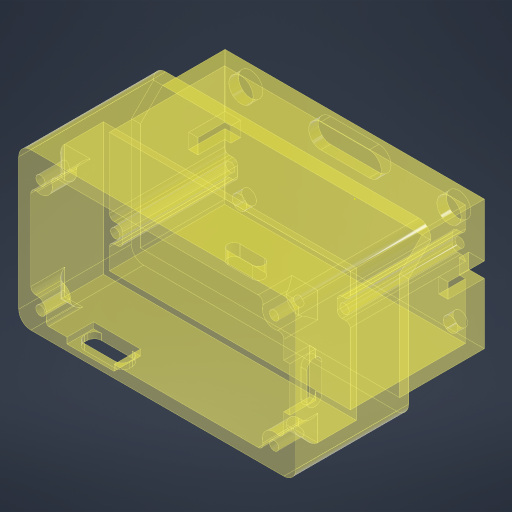
# Autodesk Inventor part: INNER
Saved by Autodesk Inventor 2024.3 (Build 283343000, 343)
## iProperties
Created: 2026-06-30
Part Number: INNER
Material: Generic
Document SubType Name: Modeling
Designer: REMOTE
Density: 1 g/cm^3
Appearance: Clear - Yellow
Author: REMOTE
Autodesk Inventor part; units mm, degrees
sketch "Sketch1" plane through (0, 0, 0) normal (0, 0, 1) x (1, 0, 0)
  line L0 (-26.8, -13.4) -> (26.8, -13.4)
  line L1 (26.8, -13.4) -> (26.8, 13.4)
  line L2 (26.8, 13.4) -> (-26.8, 13.4)
  line L3 (-26.8, 13.4) -> (-26.8, -13.4)
  line L4 (-26.8, -13.4) -> (26.8, 13.4) construction
  line L5 (26.8, -13.4) -> (-26.8, 13.4) construction
  point P0 (0, 0)
  dimension "d0" = 53.6
  dimension "d1" = 26.8
  constraints: 12 end point, 2 midpoint, 2 parallel, 1 horizontal, 1 perpendicular
  measures "d0" distance of L2.end L1.end
  measures "d1" distance of L1.end L0.end
extrude "Extrusion1" add sketch "Sketch1" along normal blind 2
sketch "Sketch2" plane through (0, 0, 2) normal (0, 0, 1) x (1, 0, 0)
  line L0 (26.8, -13.4) -> (26.8, 13.4) projected
  line L1 (26.8, 13.4) -> (-26.8, 13.4) projected
  line L2 (-26.8, 13.4) -> (-26.8, -13.4) projected
  line L3 (-26.8, -13.4) -> (26.8, -13.4) projected
  line L4 (-25.8, 12.4) -> (25.8, 12.4)
  line L5 (25.8, 12.4) -> (25.8, -12.4)
  line L6 (25.8, -12.4) -> (-25.8, -12.4)
  line L7 (-25.8, -12.4) -> (-25.8, 12.4)
  point P0 (0, 0)
  dimension "d4" = 1
  constraints: 8 end point, 3 other
  measures "d4" distance between parallel lines of L1 L4
extrude "Extrusion2" add sketch "Sketch2" along normal blind 15.5
sketch "Sketch3" plane through (0, 0, 2) normal (0, 0, 1) x (1, 0, 0)
  circle A0 centre (21.825, -10.5) radius 1.5 projected
  circle A1 centre (-21.825, -10.5) radius 1.5 projected
  point P0 (0, 0)
ref_plane "Work Plane1" through (-35.75, -21, -2) normal (0, 0, -1) x (0, 1, 0)
extrude "Extrusion3" cut sketch "Sketch3" against normal up to surface (4 mm away)
sketch "Sketch4" plane through (26.8, -13.4, 0) normal (1, 0, 0) x (0, 0, -1)
  line L0 (-7.2, 15.4) -> (0, 15.4) projected
  line L1 (-7.2, 12.9) -> (-7.2, 15.4) projected
  line L2 (0, 12.9) -> (-7.2, 12.9) projected
  line L3 (0, 26.8) -> (0, 0) projected
  line L4 (0, 15.7) -> (-7.5, 15.7)
  line L5 (-7.5, 15.7) -> (-7.5, 12.6)
  line L6 (-7.5, 12.6) -> (0, 12.6)
  point P0 (0, 13.4)
  point P1 (0, 12.6)
  dimension "d9" = 0.3
  constraints: 6 end point, 2 other
  measures "d9" distance between parallel lines of L0 L4
ref_plane "Work Plane2" through (-35.75, -21, -2) normal (-1, 0, 0) x (0, 0, 1)
extrude "Extrusion4" cut sketch "Sketch4" against normal up to surface (62.55 mm away)
sketch "Sketch5" plane through (0, 0, 0) normal (0, 0, -1) x (-1, 0, 0)
  point P0 (0, 0)
sketch "Sketch6" plane through (0, 0, 0) normal (0, 0, -1) x (-1, 0, 0)
  line L0 (26.8, -0.8) -> (-26.8, -0.8) projected
  line L1 (-26.8, 2.3) -> (26.8, 2.3) projected
  line L2 (25.8, -0.8) -> (25.8, 2.3) projected
  line L3 (-25.8, 2.3) -> (-25.8, -0.8) projected
  point P0 (0, 0)
extrude "Extrusion5" add sketch "Sketch6" against normal up to surface (2 mm away)
ref_plane "Work Plane3" through (-35.75, -21, -2) normal (0, 0, -1) x (0, 1, 0)
sketch "Sketch7" plane through (0, 0, 2) normal (0, 0, 1) x (1, 0, 0)
  line L0 (-23.9, 2) -> (-26.9, 2)
  line L1 (-26.9, -0.5) -> (-23.9, -0.5)
  line L2 (-23.9, -0.5) -> (-23.9, 2)
  line L3 (26.9, 2) -> (23.9, 2)
  line L4 (23.9, 2) -> (23.9, -0.5)
  line L5 (23.9, -0.5) -> (26.9, -0.5)
  line L6 (-26.9, 2.3) -> (-23.6, 2.3)
  line L7 (-23.6, 2.3) -> (-23.6, -0.8)
  line L8 (-23.6, -0.8) -> (-26.9, -0.8)
  line L9 (26.9, 2.3) -> (23.6, 2.3)
  line L10 (23.6, 2.3) -> (23.6, -0.8)
  line L11 (23.6, -0.8) -> (26.9, -0.8)
  line L12 (-25.8, -0.8) -> (-25.8, -12.4)
  line L13 (-25.8, -12.4) -> (25.8, -12.4)
  line L14 (25.8, -12.4) -> (25.8, -0.8)
  line L15 (25.8, 2.3) -> (25.8, -0.8)
  line L16 (25.8, 2.3) -> (25.8, 12.4)
  line L17 (25.8, 12.4) -> (-25.8, 12.4)
  line L18 (-25.8, 12.4) -> (-25.8, 2.3)
  line L19 (-25.8, -0.8) -> (-25.8, 2.3)
  circle A0 centre (-21.825, -10.5) radius 1.5
  circle A1 centre (21.825, -10.5) radius 1.5
  point P0 (0, 0)
  point P1 (25.8, -0.8)
  point P2 (-25.8, 2.3)
extrude "Extrusion6" cut sketch "Sketch7" against normal up to surface (4 mm away) contours L2 L1 L19 L0 | L0 L19 L6 L7 L8 L1 L2 | L15 L3 L4 L5 L11 L10 L9 | L15 L5 L4 L3
sketch "Sketch8" plane through (0, 0, 2) normal (0, 0, 1) x (1, 0, 0)
  circle A0 centre (21.825, -10.5) radius 1.5 projected
  circle A1 centre (-21.825, -10.5) radius 1.5 projected
  line L0 (25.8, -0.8) -> (23.6, -0.8) projected
  line L1 (23.6, -0.8) -> (23.6, 2.3) projected
  line L2 (23.6, 2.3) -> (25.8, 2.3) projected
  line L3 (25.8, 2.3) -> (25.8, 12.4) projected
  line L4 (25.8, 12.4) -> (-25.8, 12.4) projected
  line L5 (-25.8, 12.4) -> (-25.8, 2.3) projected
  line L6 (-25.8, 2.3) -> (-23.6, 2.3) projected
  line L7 (-23.6, 2.3) -> (-23.6, -0.8) projected
  line L8 (-23.6, -0.8) -> (-25.8, -0.8) projected
  line L9 (-25.8, -0.8) -> (-25.8, -12.4) projected
  line L10 (-25.8, -12.4) -> (25.8, -12.4) projected
  line L11 (25.8, -12.4) -> (25.8, -0.8) projected
  circle A2 centre (21.5, 9.8) radius 2.5
  circle A3 centre (-21.5, 9.8) radius 2.5
  point P0 (0, 0)
  dimension "d18" = 5
  dimension "d19" = 5
  dimension "d20" = 43
  dimension "d21" = 4.3
  dimension "d22" = 2.6
  dimension "d23" = 2.6
  constraints: 2 centre point
  measures "d18" diameter of A2
  measures "d19" diameter of A3
  measures "d20" distance of A2.centre A3.centre
  measures "d21" distance from line of L3 A2.centre
  measures "d22" distance from line of L4 A2.centre
  measures "d23" distance from line of L4 A3.centre
ref_plane "Work Plane4" through (-35.75, -21, -2) normal (0, 0, -1) x (0, 1, 0)
extrude "Extrusion7" cut sketch "Sketch8" against normal up to surface (4 mm away) contours A2 | A3
sketch "Sketch9" plane through (0, 0, 17.5) normal (0, 0, 1) x (1, 0, 0)
  line L0 (26.8, 13.4) -> (-26.8, 13.4) projected
  line L1 (-26.8, 13.4) -> (-26.8, -13.4) projected
  line L2 (-26.8, -13.4) -> (26.8, -13.4) projected
  line L3 (26.8, -13.4) -> (26.8, 13.4) projected
  line L4 (-25.8, 12.4) -> (25.8, 12.4) projected
  line L5 (25.8, 12.4) -> (25.8, -12.4) projected
  line L6 (25.8, -12.4) -> (-25.8, -12.4) projected
  line L7 (-25.8, -12.4) -> (-25.8, 12.4) projected
  line L8 (26.9, -13.5) -> (-26.9, -13.5) projected
  line L9 (-26.9, -13.5) -> (-26.9, 13.5) projected
  line L10 (-26.9, 13.5) -> (26.9, 13.5) projected
  line L11 (26.9, 13.5) -> (26.9, -13.5) projected
  line L12 (-28.75, 16.25) -> (28.75, 16.25) projected
  line L13 (-28.75, -16.25) -> (-28.75, 16.25) projected
  line L14 (28.75, -16.25) -> (-28.75, -16.25) projected
  line L15 (28.75, 16.25) -> (28.75, -16.25) projected
  line L16 (28.65, -16.15) -> (-28.65, -16.15)
  line L17 (-28.65, -16.15) -> (-28.65, 16.15)
  line L18 (-28.65, 16.15) -> (28.65, 16.15)
  line L19 (28.65, 16.15) -> (28.65, -16.15)
  point P0 (0, 0)
  dimension "d26" = 0.1
  constraints: 8 end point, 3 other
  measures "d26" distance between parallel lines of L15 L19
extrude "Extrusion8" add sketch "Sketch9" along normal blind 2.3 contours L3 L2 L1 L0 | L8 L9 L10 L11 | L16 L17 L18 L19
sketch "Sketch10" plane through (0, 0, 19.8) normal (0, 0, 1) x (1, 0, 0)
  line L0 (28.65, 16.15) -> (-28.65, 16.15) projected
  line L1 (-28.65, 16.15) -> (-28.65, -16.15) projected
  line L2 (-28.65, -16.15) -> (28.65, -16.15) projected
  line L3 (28.65, -16.15) -> (28.65, 16.15) projected
  line L4 (-25.8, 12.4) -> (25.8, 12.4) projected
  line L5 (25.8, 12.4) -> (25.8, -12.4) projected
  line L6 (25.8, -12.4) -> (-25.8, -12.4) projected
  line L7 (-25.8, -12.4) -> (-25.8, 12.4) projected
  line L8 (26.15, -13.65) -> (-26.15, -13.65)
  line L9 (-26.15, -13.65) -> (-26.15, 13.65)
  line L10 (-26.15, 13.65) -> (26.15, 13.65)
  line L11 (26.15, 13.65) -> (26.15, -13.65)
  point P0 (0, 0)
  dimension "d29" = 2.5
  constraints: 8 end point, 3 other
  measures "d29" distance between parallel lines of L2 L8
extrude "Extrusion9" add sketch "Sketch10" along normal blind 21 contours L3 L2 L1 L0
sketch "Sketch11" plane through (0, 0, 19.8) normal (0, 0, 1) x (1, 0, 0)
  line L0 (26.15, -13.65) -> (26.15, 13.65) projected
  line L1 (26.15, 13.65) -> (-26.15, 13.65) projected
  line L2 (-26.15, 13.65) -> (-26.15, -13.65) projected
  line L3 (-26.15, -13.65) -> (26.15, -13.65) projected
  line L4 (-25.8, 12.4) -> (25.8, 12.4) projected
  line L5 (25.8, 12.4) -> (25.8, -12.4) projected
  line L6 (25.8, -12.4) -> (-25.8, -12.4) projected
  line L7 (-25.8, -12.4) -> (-25.8, 12.4) projected
  point P0 (0, 0)
extrude "Extrusion10" add sketch "Sketch11" along normal blind 6
sketch "Sketch13" plane through (0, 0, 25.8) normal (0, 0, 1) x (1, 0, 0)
  line L0 (-26.15, 13.65) -> (26.15, 13.65) projected
  line L1 (-26.15, -13.65) -> (-26.15, 13.65) projected
  line L2 (26.15, -13.65) -> (-26.15, -13.65) projected
  line L3 (26.15, 13.65) -> (26.15, -13.65) projected
  line L4 (-25.8, 12.4) -> (25.8, 12.4) projected
  line L5 (25.8, 12.4) -> (25.8, -12.4) projected
  line L6 (25.8, -12.4) -> (-25.8, -12.4) projected
  line L7 (-25.8, -12.4) -> (-25.8, 12.4) projected
  line L8 (25.8, -12.4) -> (26.15, -12.4)
  line L9 (25.8, 12.4) -> (26.15, 12.4)
  line L10 (-25.8, -12.4) -> (-26.15, -12.4)
  line L11 (-25.8, 12.4) -> (-26.15, 12.4)
  point P0 (0, 0)
  constraints: 8 end point, 4 perpendicular, 4 point on line
extrude "Extrusion11" cut sketch "Sketch13" against normal up to surface (23.8 mm away) contours L11 L7 L10 L1 | L3 L8 L5 L9
sketch "Sketch15" plane through (0, 0, 2) normal (0, 0, 1) x (1, 0, 0)
  circle A0 centre (-21.5, 9.8) radius 2.5 projected
  circle A1 centre (21.5, 9.8) radius 2.5 projected
  circle A2 centre (21.825, -10.5) radius 1.5 projected
  circle A3 centre (-21.825, -10.5) radius 1.5 projected
  line L0 (23.6, -0.8) -> (26.15, -0.8) projected
  line L1 (23.6, -0.8) -> (23.6, 2.3) projected
  line L2 (26.15, 2.3) -> (23.6, 2.3) projected
  line L3 (26.15, 12.4) -> (26.15, 2.3) projected
  line L4 (-26.15, 12.4) -> (26.15, 12.4) projected
  line L5 (-26.15, 2.3) -> (-26.15, 12.4) projected
  line L6 (-26.15, 2.3) -> (-23.6, 2.3) projected
  line L7 (-23.6, 2.3) -> (-23.6, -0.8) projected
  line L8 (-26.15, -0.8) -> (-23.6, -0.8) projected
  line L9 (-26.15, -12.4) -> (-26.15, -0.8) projected
  line L10 (-26.15, -12.4) -> (26.15, -12.4) projected
  line L11 (26.15, -0.8) -> (26.15, -12.4) projected
  line L12 (26.15, -12.4) -> (24.9, -12.4)
  line L13 (24.9, -12.4) -> (24.9, 12.4)
  line L14 (24.9, 12.4) -> (26.15, 12.4)
  line L15 (26.15, 12.4) -> (26.15, -12.4)
  line L16 (-26.15, -12.4) -> (-24.9, -12.4)
  line L17 (-24.9, -12.4) -> (-24.9, 12.4)
  line L18 (-24.9, 12.4) -> (-26.15, 12.4)
  line L19 (-26.15, 12.4) -> (-26.15, -12.4)
  point P0 (0, 0)
  point P1 (-24.9, 2.3)
  point P2 (-24.9, -0.8)
  point P3 (24.9, 2.3)
  point P4 (24.9, -0.8)
  dimension "d36" = 1.25
  dimension "d37" = 1.25
  constraints: 16 end point, 4 parallel, 2 horizontal, 2 perpendicular, 2 point on line
  measures "d36" distance of L13.end L14.end
  measures "d37" distance of L18.end L17.end
extrude "Extrusion12" add sketch "Sketch15" along normal up to surface (23.8 mm away) contours L0 L11 L10 L13 | L13 L4 L3 L2 | L10 L9 L8 L17 | L17 L6 L5 L4
sketch "Sketch16" plane through (0, 0, 2) normal (0, 0, 1) x (1, 0, 0)
  circle A0 centre (-21.825, -10.5) radius 1.5 projected
  circle A1 centre (21.825, -10.5) radius 1.5 projected
  circle A2 centre (21.5, 9.8) radius 2.5 projected
  circle A3 centre (-21.5, 9.8) radius 2.5 projected
  line L0 (-24.9, -0.8) -> (-24.9, -12.4) projected
  line L1 (-24.9, -12.4) -> (24.9, -12.4) projected
  line L2 (24.9, -12.4) -> (24.9, -0.8) projected
  line L3 (23.6, -0.8) -> (24.9, -0.8) projected
  line L4 (23.6, -0.8) -> (23.6, 2.3) projected
  line L5 (24.9, 2.3) -> (23.6, 2.3) projected
  line L6 (24.9, 2.3) -> (24.9, 12.4) projected
  line L7 (-24.9, 12.4) -> (24.9, 12.4) projected
  line L8 (-24.9, 12.4) -> (-24.9, 2.3) projected
  line L9 (-24.9, 2.3) -> (-23.6, 2.3) projected
  line L10 (-23.6, 2.3) -> (-23.6, -0.8) projected
  line L11 (-24.9, -0.8) -> (-23.6, -0.8) projected
  circle A4 centre (23.7, 5.1) radius 0.95
  circle A5 centre (-23.7, -5.1) radius 0.95
  line L12 (22.2, 7.1) -> (25.2, 7.1)
  line L13 (25.2, 7.1) -> (25.2, 3.1)
  line L14 (25.2, 3.1) -> (22.2, 3.1)
  line L15 (22.2, 3.1) -> (22.2, 7.1)
  line L16 (22.2, 7.1) -> (25.2, 3.1) construction
  line L17 (25.2, 7.1) -> (22.2, 3.1) construction
  line L18 (-22.2, -3.1) -> (-25.2, -3.1)
  line L19 (-25.2, -3.1) -> (-25.2, -7.1)
  line L20 (-25.2, -7.1) -> (-22.2, -7.1)
  line L21 (-22.2, -7.1) -> (-22.2, -3.1)
  line L22 (-22.2, -3.1) -> (-25.2, -7.1) construction
  line L23 (-25.2, -3.1) -> (-22.2, -7.1) construction
  point P0 (0, 0)
  point P1 (-24.9, -3.1)
  point P2 (-24.9, -7.1)
  point P3 (24.9, 3.1)
  point P4 (24.9, 7.1)
  dimension "d40" = 1.9
  dimension "d41" = 1.2
  dimension "d42" = 7.3
  dimension "d43" = 1.9
  dimension "d44" = 1.2
  dimension "d45" = 7.3
  dimension "d46" = 3
  dimension "d47" = 4
  dimension "d48" = 3
  dimension "d49" = 4
  constraints: 24 end point, 4 midpoint, 4 parallel, 2 centre point, 2 horizontal, 2 perpendicular
  measures "d40" diameter of A4
  measures "d41" distance from line of L6 A4.centre
  measures "d42" distance from line of L7 A4.centre
  measures "d43" diameter of A5
  measures "d44" distance from line of L0 A5.centre
  measures "d45" distance from line of L1 A5.centre
  measures "d46" distance of L13.end L14.end
  measures "d47" distance of L12.end L13.end
  measures "d48" distance of L20.end L19.end
  measures "d49" distance of L19.end L18.end
extrude "Extrusion13" add sketch "Sketch16" along normal up to surface (23.8 mm away) contours L18 L21 L20 L0 | L6 L14 L15 L12
fillet "Fillet1" radius 1 8 edges at (22.2, 7.1, 13.9) (24.9, 7.1, 13.9) (22.2, 3.1, 13.9) (24.9, 3.1, 13.9) (-24.9, -3.1, 13.9) (-22.2, -3.1, 13.9) (-22.2, -7.1, 13.9) (-24.9, -7.1, 13.9)
sketch "Sketch17" plane through (0, 0, 40.8) normal (0, 0, 1) x (1, 0, 0)
  line L0 (-28.65, 16.15) -> (-28.65, -16.15) projected
  line L1 (-28.65, -16.15) -> (28.65, -16.15) projected
  line L2 (28.65, -16.15) -> (28.65, 16.15) projected
  line L3 (28.65, 16.15) -> (-28.65, 16.15) projected
  line L4 (26.15, -13.65) -> (-26.15, -13.65) projected
  line L5 (-26.15, -13.65) -> (-26.15, 13.65) projected
  line L6 (-26.15, 13.65) -> (26.15, 13.65) projected
  line L7 (26.15, 13.65) -> (26.15, -13.65) projected
  line L8 (26.15, -13.65) -> (24.15, -13.65)
  line L9 (26.15, -13.65) -> (-26.15, -13.65) projected
  line L10 (24.15, -13.65) -> (24.15, -11.65)
  circle A0 centre (24.15, -11.65) radius 0.95
  circle A1 centre (24.15, -11.65) radius 2.45
  point P0 (0, 0)
  point P1 (26.15, -10.2349)
  point P2 (22.7349, -13.65)
  dimension "d104" = 2
  dimension "d105" = 2
  dimension "d106" = 1.9
  dimension "d107" = 1.5
  constraints: 4 end point, 2 centre point, 1 coincident, 1 perpendicular, 1 point on line
  measures "d104" distance of L4.start L8.end
  measures "d105" distance of L8.end L10.end
  measures "d106" diameter of A0
  measures "d107" radial gap between concentric circles of A0 A1
fillet "Fillet3" radius 2.5 4 edges at (-28.65, -16.15, 29.15) (28.65, -16.15, 29.15) (28.65, 16.15, 29.15) (-28.65, 16.15, 29.15)
sketch "Sketch20" plane through (0, 0, 40.8) normal (0, 0, 1) x (1, 0, 0)
  line L0 (-18.27, -14.5) -> (-18.27, -12.6) projected
  line L1 (-9.33, -12.6) -> (-9.33, -14.5) projected
  line L2 (27, 4.21) -> (20.1, 4.21)
  line L3 (27, 4.21) -> (27, 2.89) projected
  line L4 (27, -2.89) -> (27, 2.89) projected
  line L5 (27, -2.89) -> (27, -4.21) projected
  line L6 (27, -4.21) -> (20.1, -4.21)
  line L7 (-16.9746, -14.5) -> (-18.27, -14.5) projected
  line L8 (-16.9746, -14.5) -> (-13.3125, -14.5) projected
  line L9 (-13.2625, -14.5) -> (-10.6254, -14.5) projected
  line L10 (-16.9746, -14.5) -> (-10.6254, -14.5) projected
  line L11 (-9.33, -14.5) -> (-10.6254, -14.5) projected
  line L12 (-8.93, -12.6) -> (-8.93, -14.9)
  line L13 (-8.93, -14.9) -> (-10.6254, -14.9)
  line L14 (-13.2625, -14.9) -> (-10.6254, -14.9)
  line L15 (-16.9746, -14.9) -> (-10.6254, -14.9)
  line L16 (-16.9746, -14.9) -> (-18.67, -14.9)
  line L17 (-18.67, -14.9) -> (-18.67, -12.6)
  line L18 (20.1, 4.61) -> (27.4, 4.61)
  line L19 (27.4, 4.61) -> (27.4, 2.89)
  line L20 (27.4, 2.89) -> (27.4, -2.89)
  line L21 (27.4, -2.89) -> (27.4, -4.61)
  line L22 (27.4, -4.61) -> (20.1, -4.61)
  arc A0 (28.65, 13.65) -> (26.15, 16.15) centre (26.15, 13.65) ccw projected
  line L23 (28.65, -13.65) -> (28.65, 13.65) projected
  arc A1 (26.15, -16.15) -> (28.65, -13.65) centre (26.15, -13.65) ccw projected
  line L24 (-26.15, -16.15) -> (26.15, -16.15) projected
  arc A2 (-28.65, -13.65) -> (-26.15, -16.15) centre (-26.15, -13.65) ccw projected
  line L25 (-28.65, 13.65) -> (-28.65, -13.65) projected
  arc A3 (-26.15, 16.15) -> (-28.65, 13.65) centre (-26.15, 13.65) ccw projected
  line L26 (26.15, 16.15) -> (-26.15, 16.15) projected
  line L27 (-23, -6.2221) -> (-23, 2.7221) projected
  line L28 (-21.5042, 10.2) -> (-5.8, 10.2) projected
  arc A4 (-4.6002, 9.0243) -> (-5.8, 10.2) centre (-5.8, 9) ccw projected
  arc A5 (-4.6002, 9.0243) -> (-4.6, 7.7755) centre (-4.1, 8.4) ccw projected
  line L29 (-4.6, -2.3745) -> (-4.6, -9.9) projected
  line L30 (-4.6, -9.9) -> (22.0278, -9.9) projected
  line L31 (22.0278, -8.9) -> (-2.5, -8.9) projected
  line L32 (-2.5, -8.9) -> (-2.5, -6.4889) projected
  arc A6 (-2.5, -6.4889) -> (-0.5, -4.7) centre (-2.3, -4.7) ccw projected
  line L33 (-0.5, -4.7) -> (-0.5, 4.7) projected
  arc A7 (-0.5, 4.7) -> (-2.5, 6.4889) centre (-2.3, 4.7) ccw projected
  line L34 (-2.5, 6.4889) -> (-2.5, 8.9) projected
  line L35 (-2.5, 8.9) -> (22.0278, 8.9) projected
  line L36 (22.0278, 9.9) -> (-3.4676, 9.9) projected
  arc A8 (-3.4676, 9.9) -> (-5.8, 11.5) centre (-5.8, 9) ccw projected
  line L37 (-5.8, 11.5) -> (-21.5042, 11.5) projected
  arc A9 (28.65, 13.65) -> (26.15, 16.15) centre (26.15, 13.65) ccw projected
  line L38 (28.65, -13.65) -> (28.65, 13.65) projected
  arc A10 (26.15, -16.15) -> (28.65, -13.65) centre (26.15, -13.65) ccw projected
  line L39 (-26.15, -16.15) -> (26.15, -16.15) projected
  arc A11 (-28.65, -13.65) -> (-26.15, -16.15) centre (-26.15, -13.65) ccw projected
  line L40 (-28.65, 13.65) -> (-28.65, -13.65) projected
  arc A12 (-26.15, 16.15) -> (-28.65, 13.65) centre (-26.15, 13.65) ccw projected
  line L41 (26.15, 16.15) -> (-26.15, 16.15) projected
  line L42 (-23, -6.2221) -> (-23, 2.7221) projected
  line L43 (-21.5042, 10.2) -> (-5.8, 10.2) projected
  arc A13 (-4.6002, 9.0243) -> (-5.8, 10.2) centre (-5.8, 9) ccw projected
  arc A14 (-4.6002, 9.0243) -> (-4.6, 7.7755) centre (-4.1, 8.4) ccw projected
  line L44 (-4.6, -2.3745) -> (-4.6, -9.9) projected
  line L45 (-4.6, -9.9) -> (22.0278, -9.9) projected
  line L46 (22.0278, -8.9) -> (-2.5, -8.9) projected
  line L47 (-2.5, -8.9) -> (-2.5, -6.4889) projected
  arc A15 (-2.5, -6.4889) -> (-0.5, -4.7) centre (-2.3, -4.7) ccw projected
  line L48 (-0.5, -4.7) -> (-0.5, 4.7) projected
  arc A16 (-0.5, 4.7) -> (-2.5, 6.4889) centre (-2.3, 4.7) ccw projected
  line L49 (-2.5, 6.4889) -> (-2.5, 8.9) projected
  line L50 (-2.5, 8.9) -> (22.0278, 8.9) projected
  line L51 (22.0278, 9.9) -> (-3.4676, 9.9) projected
  arc A17 (-3.4676, 9.9) -> (-5.8, 11.5) centre (-5.8, 9) ccw projected
  line L52 (-5.8, 11.5) -> (-21.5042, 11.5) projected
  line L53 (26.15, -13.65) -> (-26.15, -13.65) projected
  line L54 (26.15, 13.65) -> (26.15, -13.65) projected
  line L55 (13.1442, 5) -> (13.1442, -5) projected
  line L56 (13.1442, -5) -> (24.1442, -5) projected
  line L57 (24.1442, -5) -> (24.1442, 5) projected
  line L58 (24.1442, 5) -> (13.1442, 5) projected
  line L59 (13.1442, 5) -> (13.1442, -5) projected
  line L60 (13.1442, -5) -> (24.1442, -5) projected
  line L61 (24.1442, -5) -> (24.1442, 5) projected
  line L62 (24.1442, 5) -> (13.1442, 5) projected
  circle A18 centre (24.15, 11.65) radius 1.05 projected
  circle A19 centre (-24.15, -11.65) radius 1.05 projected
  circle A20 centre (24.15, -11.65) radius 1.05 projected
  circle A21 centre (24.15, 11.65) radius 1.05 projected
  circle A22 centre (-24.15, -11.65) radius 1.05 projected
  circle A23 centre (24.15, -11.65) radius 1.05 projected
  circle A24 centre (-24.15, 11.65) radius 1.05 projected
  circle A25 centre (-24.15, 11.65) radius 1.05 projected
  line L63 (22.0278, -9.9) -> (22.0278, -8.9) projected
  line L64 (22.0278, 8.9) -> (22.0278, 9.9) projected
  line L65 (-21.5042, 11.5) -> (-21.5042, 10.2) projected
  line L66 (-25.3, -8.7322) -> (-23, -8.7322) projected
  circle A26 centre (-24.15, 11.65) radius 1.05 projected
  circle A27 centre (-24.15, 11.65) radius 1.05 projected
  line L67 (22.0278, -9.9) -> (22.0278, -8.9) projected
  line L68 (22.0278, 8.9) -> (22.0278, 9.9) projected
  line L69 (-21.5042, 11.5) -> (-21.5042, 10.2) projected
  line L70 (-25.3, -8.7322) -> (-23, -8.7322) projected
  circle A28 centre (24.3, -7.2) radius 1.6 projected
  circle A29 centre (24.3, 7.2) radius 1.6 projected
  circle A30 centre (24.3, -7.2) radius 1.6 projected
  circle A31 centre (24.3, 7.2) radius 1.6 projected
  arc A32 (-23, -7.4379) -> (-23, -6.2221) centre (-23.52, -6.83) ccw projected
  arc A33 (-23, 2.7221) -> (-23, 3.9379) centre (-23.52, 3.33) ccw projected
  line L71 (-23, 3.9379) -> (-23, 7.0734) projected
  line L72 (-23, 7.0734) -> (-25.3, 7.0734) projected
  line L73 (-25.3, 7.0734) -> (-25.3, -8.7322) projected
  line L74 (-23, -8.7322) -> (-23, -7.4379) projected
  arc A34 (-4.6, -1.1255) -> (-4.6, -2.3745) centre (-4.1, -1.75) ccw projected
  line L75 (-4.6, 7.7755) -> (-4.6, -1.1255) projected
  arc A35 (-23, -7.4379) -> (-23, -6.2221) centre (-23.52, -6.83) ccw projected
  arc A36 (-23, 2.7221) -> (-23, 3.9379) centre (-23.52, 3.33) ccw projected
  line L76 (-23, 3.9379) -> (-23, 7.0734) projected
  line L77 (-23, 7.0734) -> (-25.3, 7.0734) projected
  line L78 (-25.3, 7.0734) -> (-25.3, -8.7322) projected
  line L79 (-23, -8.7322) -> (-23, -7.4379) projected
  arc A37 (-4.6, -1.1255) -> (-4.6, -2.3745) centre (-4.1, -1.75) ccw projected
  line L80 (-4.6, 7.7755) -> (-4.6, -1.1255) projected
  point P0 (0, 0)
  point P1 (-24.3, 7.0734)
  point P2 (-23, 7.8708)
  point P3 (24.2, -13.65)
  point P4 (-24.2, -13.65)
  point P5 (26.15, 11.7)
  point P6 (26.15, -11.7)
  point P7 (-18.67, -13.65)
  point P8 (-8.93, -13.65)
  point P9 (26.15, -4.61)
  point P10 (26.15, 4.61)
  point P11 (-23.539, 10.7961)
  point P12 (-23.3753, 10.9413)
  point P13 (-24.9191, 9.1141)
  point P14 (-24.1291, 9.0001)
  point P15 (-24.9181, 9.1138)
  point P16 (-24.3, -8.7322)
  dimension "d69" = 0.4
  dimension "d70" = 0.4
  dimension "d71" = 0.4
  dimension "d72" = 0.4
  dimension "d73" = 0.4
  constraints: 26 end point, 2 horizontal, 2 parallel, 9 other
  measures "d69" distance between parallel lines of L1 L12
  measures "d70" distance between parallel lines of L9 L14
  measures "d71" distance between parallel lines of L10 L15
  measures "d72" distance between parallel lines of L7 L16
  measures "d73" distance between parallel lines of L2 L18
extrude "Extrusion17" cut sketch "Sketch20" against normal blind 6 contours L7 L8 L10 L9 L11 L1 L53 L12 L13 L14 L15 L16 L17 L0 | L0 L53 L1 L11 L9 L10 L8 L7 | L3 L4 L5 L6 L54 L2 | L2 L54 L18 L19 L20 L21 L22 L6 L5 L4 L3
sketch "Sketch21" plane through (-26.15, -16.15, 17.5) normal (0, -1, 0) x (1, 0, 0)
  arc A0 (9.1754, 21.2) -> (7.88, 19.9046) centre (9.1754, 19.9046) ccw projected
  line L0 (7.88, 19.3354) -> (7.88, 19.9046) projected
  arc A1 (7.88, 19.3354) -> (9.1754, 18.04) centre (9.1754, 19.3354) ccw projected
  line L1 (15.5246, 18.04) -> (9.1754, 18.04) projected
  arc A2 (15.5246, 18.04) -> (16.82, 19.3354) centre (15.5246, 19.3354) ccw projected
  line L2 (16.82, 19.9046) -> (16.82, 19.3354) projected
  arc A3 (16.82, 19.9046) -> (15.5246, 21.2) centre (15.5246, 19.9046) ccw projected
  line L3 (12.8875, 21.2) -> (15.5246, 21.2) projected
  line L4 (12.5875, 21.2) -> (12.8875, 21.2) projected
  line L5 (9.1754, 21.2) -> (12.8375, 21.2) projected
  point P0 (26.15, -17.5)
extrude "Extrusion18" cut sketch "Sketch21" against normal blind 4
sketch "Sketch22" plane through (-26.15, -16.15, 17.5) normal (0, -1, 0) x (1, 0, 0)
  arc A0 (7.88, 19.3354) -> (9.1754, 18.04) centre (9.1754, 19.3354) ccw projected
  line L0 (7.88, 19.3354) -> (7.88, 19.9046) projected
  arc A1 (9.1754, 21.2) -> (7.88, 19.9046) centre (9.1754, 19.9046) ccw projected
  line L1 (9.1754, 21.2) -> (15.5246, 21.2) projected
  arc A2 (16.82, 19.9046) -> (15.5246, 21.2) centre (15.5246, 19.9046) ccw projected
  line L2 (16.82, 19.9046) -> (16.82, 19.3354) projected
  arc A3 (15.5246, 18.04) -> (16.82, 19.3354) centre (15.5246, 19.3354) ccw projected
  line L3 (15.5246, 18.04) -> (9.1754, 18.04) projected
  line L4 (52.3, 23.3) -> (52.3, 0) projected
  line L5 (0, 23.3) -> (52.3, 23.3) projected
  line L6 (0, 0) -> (0, 23.3) projected
  line L7 (0, 0) -> (52.3, 0) projected
  line L8 (15.5246, 21.4) -> (9.1754, 21.4)
  arc A4 (9.1754, 21.4) -> (7.68, 19.9046) centre (9.1754, 19.9046) ccw
  line L9 (7.68, 19.9046) -> (7.68, 19.3354)
  arc A5 (7.68, 19.3354) -> (9.1754, 17.84) centre (9.1754, 19.3354) ccw
  line L10 (9.1754, 17.84) -> (15.5246, 17.84)
  arc A6 (15.5246, 17.84) -> (17.02, 19.3354) centre (15.5246, 19.3354) ccw
  line L11 (17.02, 19.3354) -> (17.02, 19.9046)
  arc A7 (17.02, 19.9046) -> (15.5246, 21.4) centre (15.5246, 19.9046) ccw
  point P0 (26.15, -17.5)
  dimension "d78" = 0.2
  constraints: 8 end point, 8 point on circle, 4 centre point, 7 other
  measures "d78" radial gap between concentric circles of A2 A7
extrude "Extrusion19" cut sketch "Sketch22" against normal blind 4 contours A7 L11 A6 L10 A5 L9 A4 L8
sketch "Sketch24" plane through (-26.15, 16.15, 17.5) normal (0, 1, 0) x (1, 0, 0)
  line L0 (43, -19.8) -> (44, -19.8) projected
  line L1 (38, -19.8) -> (39, -19.8) projected
  line L2 (43.5, -19.8) -> (38.5, -19.8) construction
  line L3 (43.5, -18.55) -> (38.5, -18.55)
  line L4 (38.5, -21.05) -> (43.5, -21.05)
  arc A0 (43.5, -21.05) -> (43.5, -18.55) centre (43.5, -19.8) ccw
  arc A1 (38.5, -18.55) -> (38.5, -21.05) centre (38.5, -19.8) ccw
  point P0 (26.15, 17.5)
  point P1 (41, -19.8)
  dimension "d84" = 2.5
  constraints: 8 end point, 4 point on circle, 4 tangent, 3 midpoint, 2 centre point, 1 parallel
  measures "d84" diameter of A1
extrude "Extrusion21" cut sketch "Sketch24" against normal blind 4
sketch "Sketch25" plane through (28.65, -13.65, 17.5) normal (1, 0, 0) x (0, 0, -1)
  arc A0 (-18.16, 16.54) -> (-20.8, 16.54) centre (-19.48, 16.54) ccw projected
  line L0 (-18.16, 16.54) -> (-18.16, 10.76) projected
  arc A1 (-20.8, 10.76) -> (-18.16, 10.76) centre (-19.48, 10.76) ccw projected
  line L1 (-20.8, 10.76) -> (-20.8, 16.54) projected
  arc A2 (-17.96, 16.54) -> (-21, 16.54) centre (-19.48, 16.54) ccw
  line L2 (-17.96, 16.54) -> (-17.96, 10.76)
  arc A3 (-21, 10.76) -> (-17.96, 10.76) centre (-19.48, 10.76) ccw
  line L3 (-21, 10.76) -> (-21, 16.54)
  point P0 (17.5, 13.65)
  dimension "d87" = 0.2
  constraints: 4 end point, 4 point on circle, 2 centre point, 3 other
  measures "d87" distance between parallel lines of L1 L3
extrude "Extrusion22" cut sketch "Sketch25" against normal up to surface (2.5 mm away) contours L0 A1 L1 A0 | L2 A3 L3 A2
sketch "Sketch26" plane through (0, 0, 34.8) normal (0, 0, 1) x (1, 0, 0)
  line L0 (-18.67, -14.9) -> (-18.67, -13.65) projected
  line L1 (-8.93, -14.9) -> (-18.67, -14.9) projected
  line L2 (-8.93, -13.65) -> (-8.93, -14.9) projected
  line L3 (-18.67, -13.65) -> (-8.93, -13.65) projected
  line L4 (27.4, -4.61) -> (26.15, -4.61) projected
  line L5 (27.4, 4.61) -> (27.4, -4.61) projected
  line L6 (26.15, 4.61) -> (27.4, 4.61) projected
  line L7 (26.15, -4.61) -> (26.15, 4.61) projected
  point P0 (0, 0)
extrude "Extrusion23" add sketch "Sketch26" along normal up to surface (0.54 mm away)
sketch "Sketch27" plane through (26.15, 4.61, 35.34) normal (0, 0, 1) x (1, 0, 0)
  line L0 (1.25, 0) -> (1.25, -9.22) projected
  line L1 (0, 0) -> (1.25, 0) projected
  line L2 (1.25, -9.22) -> (0, -9.22) projected
  line L3 (0, 0) -> (0, -9.22) projected
  point P0 (-26.15, -4.61)
extrude "Extrusion24" add sketch "Sketch27" along normal up to surface (0.12 mm away)
sketch "Sketch28" plane through (0, 0, 0) normal (0, 0, -1) x (-1, 0, 0)
  circle A0 centre (-21.5, 9.8) radius 2.5 construction
  circle A1 centre (21.5, 9.8) radius 2.5 construction
  line L0 (-21.5, 9.8) -> (21.5, 9.8) construction
  line L1 (0, 9.8) -> (-5, 9.8) construction
  line L2 (0, 9.8) -> (5, 9.8) construction
  line L3 (-5, 9.8) -> (5, 9.8) construction
  line L4 (-5, 7.3) -> (5, 7.3)
  line L5 (5, 12.3) -> (-5, 12.3)
  arc A2 (-5, 12.3) -> (-5, 7.3) centre (-5, 9.8) ccw
  arc A3 (5, 7.3) -> (5, 12.3) centre (5, 9.8) ccw
  point P0 (0, 0)
  dimension "d94" = 5
  dimension "d95" = 5
  dimension "d96" = 5
  constraints: 14 end point, 4 point on circle, 4 tangent, 2 centre point, 2 midpoint, 2 point on line, 1 collinear, 1 horizontal, 1 parallel
  measures "d94" distance of L1.start L1.end
  measures "d95" distance of L1.start L2.end
  measures "d96" diameter of A3
extrude "Extrusion25" cut sketch "Sketch28" against normal up to surface (2 mm away)
sketch "Sketch29" plane through (0, 0, 17.5) normal (0, 0, -1) x (-1, 0, 0)
  line L0 (-26.8, -13.4) -> (-26.8, 13.4) projected
  line L1 (-26.8, 13.4) -> (26.8, 13.4) projected
  line L2 (26.8, 13.4) -> (26.8, -13.4) projected
  line L3 (26.8, -13.4) -> (-26.8, -13.4) projected
  arc A0 (28.65, 13.65) -> (26.15, 16.15) centre (26.15, 13.65) ccw projected
  line L4 (-26.15, 16.15) -> (26.15, 16.15) projected
  arc A1 (-26.15, 16.15) -> (-28.65, 13.65) centre (-26.15, 13.65) ccw projected
  line L5 (-28.65, -13.65) -> (-28.65, 13.65) projected
  arc A2 (-28.65, -13.65) -> (-26.15, -16.15) centre (-26.15, -13.65) ccw projected
  line L6 (26.15, -16.15) -> (-26.15, -16.15) projected
  arc A3 (26.15, -16.15) -> (28.65, -13.65) centre (26.15, -13.65) ccw projected
  line L7 (28.65, 13.65) -> (28.65, -13.65) projected
  line L8 (-26.8, -13.4) -> (-26.8, 13.4) projected
  line L9 (-26.8, 13.4) -> (-28.65, 13.4)
  line L10 (26.8, 13.4) -> (28.65, 13.4)
  point P0 (0, 0)
  constraints: 4 end point, 2 point on line, 1 horizontal
extrude "Extrusion26" add sketch "Sketch29" along normal blind 4.6 contours L9 L5 A1 L4 A0 L7 L10 L1
chamfer "Chamfer1" distance 4.6 angle 45 2 edges at (27.725, 13.4, 17.5) (-27.725, 13.4, 17.5)
extrude "Extrusion27" add sketch "Sketch17" against normal blind 5 contours L4 A1 L7 | L4 A1 L7
mirror "Mirror1" about plane through (0, 0, 0) normal (1, 0, 0) of "Extrusion27"
mirror "Mirror2" about plane through (0, 0, 0) normal (0, 1, 0) of "Extrusion27", "Mirror1"
fillet "Fillet4" radius 1 8 edges at (26.15, -10.2349, 38.3) (22.7349, -13.65, 38.3) (22.7349, 13.65, 38.3) (26.15, 10.2349, 38.3) (-22.7349, -13.65, 38.3) (-26.15, -10.2349, 38.3) (-26.15, 10.2349, 38.3) (-22.7349, 13.65, 38.3)
sketch "Sketch30" plane through (0, 0, 40.8) normal (0, 0, 1) x (1, 0, 0)
  circle A0 centre (-24.15, 11.65) radius 0.95 projected
  circle A1 centre (24.15, 11.65) radius 0.95 projected
  circle A2 centre (-24.15, -11.65) radius 0.95 projected
  circle A3 centre (24.15, -11.65) radius 0.95 projected
  line L0 (-18.67, -14.9) -> (-18.67, -13.65) projected
  line L1 (-18.67, -13.65) -> (-20.8481, -13.65) projected
  arc A4 (-21.8052, -12.3601) -> (-20.8481, -13.65) centre (-20.8481, -12.65) ccw projected
  arc A5 (-21.8052, -12.3601) -> (-24.8601, -9.3052) centre (-24.15, -11.65) ccw projected
  arc A6 (-26.15, -8.3481) -> (-24.8601, -9.3052) centre (-25.15, -8.3481) ccw projected
  line L2 (-26.15, -8.3481) -> (-26.15, 8.3481) projected
  arc A7 (-24.8601, 9.3052) -> (-26.15, 8.3481) centre (-25.15, 8.3481) ccw projected
  arc A8 (-24.8601, 9.3052) -> (-21.8052, 12.3601) centre (-24.15, 11.65) ccw projected
  arc A9 (-20.8481, 13.65) -> (-21.8052, 12.3601) centre (-20.8481, 12.65) ccw projected
  line L3 (-20.8481, 13.65) -> (20.8481, 13.65) projected
  arc A10 (21.8052, 12.3601) -> (20.8481, 13.65) centre (20.8481, 12.65) ccw projected
  arc A11 (21.8052, 12.3601) -> (24.8601, 9.3052) centre (24.15, 11.65) ccw projected
  arc A12 (26.15, 8.3481) -> (24.8601, 9.3052) centre (25.15, 8.3481) ccw projected
  line L4 (26.15, 8.3481) -> (26.15, 4.61) projected
  line L5 (26.15, 4.61) -> (27.4, 4.61) projected
  line L6 (27.4, 4.61) -> (27.4, -4.61) projected
  line L7 (27.4, -4.61) -> (26.15, -4.61) projected
  line L8 (26.15, -4.61) -> (26.15, -8.3481) projected
  arc A13 (24.8601, -9.3052) -> (26.15, -8.3481) centre (25.15, -8.3481) ccw projected
  arc A14 (24.8601, -9.3052) -> (21.8052, -12.3601) centre (24.15, -11.65) ccw projected
  arc A15 (20.8481, -13.65) -> (21.8052, -12.3601) centre (20.8481, -12.65) ccw projected
  line L9 (20.8481, -13.65) -> (-8.93, -13.65) projected
  line L10 (-8.93, -13.65) -> (-8.93, -14.9) projected
  line L11 (-8.93, -14.9) -> (-18.67, -14.9) projected
  arc A16 (-26.15, 16.15) -> (-28.65, 13.65) centre (-26.15, 13.65) ccw projected
  line L12 (-28.65, 13.65) -> (-28.65, -13.65) projected
  arc A17 (-28.65, -13.65) -> (-26.15, -16.15) centre (-26.15, -13.65) ccw projected
  line L13 (-26.15, -16.15) -> (26.15, -16.15) projected
  arc A18 (26.15, -16.15) -> (28.65, -13.65) centre (26.15, -13.65) ccw projected
  line L14 (28.65, -13.65) -> (28.65, 13.65) projected
  arc A19 (28.65, 13.65) -> (26.15, 16.15) centre (26.15, 13.65) ccw projected
  line L15 (26.15, 16.15) -> (-26.15, 16.15) projected
  line L16 (-22.8, -8.92) -> (-22.7349, -13.65)
  line L17 (26.15, -13.65) -> (-26.15, -13.65) projected
  line L18 (-23, -8.9228) -> (-22.9349, -13.6528)
  point P0 (0, 0)
  point P1 (-22.9922, -9.4909)
  point P2 (-22.9349, -13.65)
  dimension "d111" = 0.2
  constraints: 4 end point, 1 parallel, 1 point on line, 1 other
  measures "d111" distance between parallel lines of L16 L18
extrude "Extrusion28" cut sketch "Sketch30" against normal blind 5 contours L17 L16 A5 A4 | L17 L18 A5 L16
fillet "Fillet5" radius 2 1 edges at (-22.9922, -9.4909, 38.3)
fillet "Fillet6" radius 0.5 1 edges at (-22.9349, -13.65, 38.3)
sketch "Sketch31" plane through (0, 0, 25.8) normal (0, 0, 1) x (1, 0, 0)
  line L0 (-24.9, 2.3) -> (-26.15, 2.3) projected
  line L1 (-26.15, -0.8) -> (-24.9, -0.8) projected
  line L2 (26.15, 2.3) -> (24.9, 2.3) projected
  line L3 (24.9, -0.8) -> (26.15, -0.8) projected
  line L4 (-26.15, 2.3) -> (-24.9, 2.3)
  line L5 (-24.9, 2.3) -> (-24.9, -0.8)
  line L6 (-24.9, -0.8) -> (-26.15, -0.8)
  line L7 (-26.15, -0.8) -> (-26.15, 2.3)
  line L8 (26.15, 2.3) -> (24.9, 2.3)
  line L9 (24.9, 2.3) -> (24.9, -0.8)
  line L10 (24.9, -0.8) -> (26.15, -0.8)
  line L11 (26.15, -0.8) -> (26.15, 2.3)
  point P0 (0, 0)
  constraints: 16 end point, 4 parallel, 2 horizontal, 2 perpendicular
extrude "Extrusion29" add sketch "Sketch31" against normal up to surface (18.3 mm away)
fillet "Fillet7" radius 2 9 edges at (26.15, 10.9991, 35.8) (23.4991, 13.65, 35.8) (-23.4991, 13.65, 35.8) (-26.15, 10.9991, 35.8) (-26.15, -10.9991, 35.8) (-22.6883, -13.65, 35.8) (-24.5425, -13.65, 35.8) (26.15, -10.9991, 35.8) (23.4991, -13.65, 35.8)
body "Solid1"
